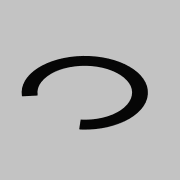
# Autodesk Inventor part: carbon
Saved by Autodesk Inventor 2015 SP1 (Build 190203100, 203)
## iProperties
Created: 2015-06-25
Part Number: carbon
Material: Generic
Document SubType Name: Modeling
Designer: Peter Mulkers
Density: 1 g/cm^3
Appearance: Black
Author: Peter Mulkers
Autodesk Inventor part; units mm, degrees
ref_plane "YZ Plane" through (0, 0, 0) normal (1, 0, 0) x (0, 1, 0)
ref_plane "XZ Plane" through (0, 0, 0) normal (0, 1, 0) x (-1, 0, 0)
ref_plane "XY Plane" through (0, 0, 0) normal (0, 0, 1) x (1, 0, 0)
sketch "Sketch1" plane through (0, 0, 0) normal (0, 0, 1) x (1, 0, 0)
  arc A0 (4.8209, -5.7453) -> (-4.8209, -5.7453) centre (0, 0) ccw
  arc A1 (6.4279, -7.6604) -> (-6.4279, -7.6604) centre (0, 0) ccw
  line L0 (0, -11.1925) -> (0, 13.5321) construction
  line L1 (0, 0) -> (-6.4279, -7.6604) construction
  line L2 (-6.4279, -7.6604) -> (-4.8209, -5.7453)
  line L3 (0, 0) -> (6.4279, -7.6604) construction
  line L4 (6.4279, -7.6604) -> (4.8209, -5.7453)
  dimension "d0" = 15
  dimension "d1" = 20
  dimension "d2" = 40
  constraints: 8 end point, 4 point on circle, 2 centre point, 2 coincident, 2 point on line, 1 symmetric about line
  measures "d0" diameter of A0
  measures "d1" diameter of A1
  measures "d2" angle of L0 L1
extrude "Extrusion1" add sketch "Sketch1" along normal blind 0.25
fillet "Fillet2" radius 0.2 4 edges at (0, 10, 0) (5.6244, -6.7029, 0) (0, 7.5, 0) (-5.6244, -6.7029, 0)
body "Solid1"
